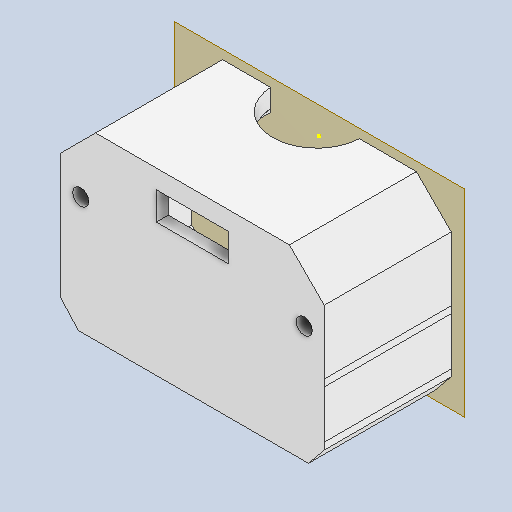
# Autodesk Inventor part: деталька крепления часть первая
Saved by Autodesk Inventor 2024.2 (Build 282272000, 272)
## iProperties
Created: 2026-09-02
Part Number: деталька крепления часть первая
Material: PLA
Document SubType Name: Modeling
Designer: katya_notebook
Density: 1.24 g/cm^3
Appearance: Типовые
Author: katya_notebook
Autodesk Inventor part; units mm, degrees
ref_plane "YZ Plane" through (0, 0, 0) normal (1, 0, 0) x (0, 1, 0)
ref_plane "РабПлоскость1" through (0, 0, 0) normal (0, 0, 1) x (1, 0, 0)
sketch "Эскиз1" plane through (0, 0, 0) normal (0, 0, 1) x (1, 0, 0)
  line L0 (-22.9, -16.3497) -> (-31.9, -16.3497) projected
  arc A0 (-22.9, -16.3497) -> (-20.9, -14.3497) centre (-22.9, -14.3497) ccw projected
  line L1 (-20.9, -6.3497) -> (-20.9, -14.3497) projected
  arc A1 (-18.9, -4.3497) -> (-20.9, -6.3497) centre (-18.9, -6.3497) ccw projected
  line L2 (-18.9, -4.3497) -> (-17.916, -4.3497) projected
  line L3 (-17.916, -4.3497) -> (-12.1991, -1.0491) projected
  line L4 (9.9767, 0.1785) -> (17.8199, -4.3497) projected
  line L5 (17.8199, -4.3497) -> (18.9, -4.3497) projected
  arc A2 (20.9, -6.3497) -> (18.9, -4.3497) centre (18.9, -6.3497) ccw projected
  line L6 (20.9, -14.3497) -> (20.9, -6.3497) projected
  arc A3 (20.9, -14.3497) -> (22.9, -16.3497) centre (22.9, -14.3497) ccw projected
  line L7 (31.9, -16.3497) -> (22.9, -16.3497) projected
  line L8 (31.9, -20.3042) -> (31.9, -16.3497) projected
  line L9 (31.9036, -22.0088) -> (31.9, -20.3042) projected
  line L10 (31.9036, -33.957) -> (31.9036, -22.0088) projected
  line L11 (31.9065, -35.3056) -> (31.9036, -33.957) projected
  line L12 (28.483, -39.5052) -> (31.9065, -35.3056) projected
  line L13 (-28.0526, -39.5052) -> (28.483, -39.5052) projected
  line L14 (-31.8964, -35.2742) -> (-28.0526, -39.5052) projected
  line L15 (-31.8964, -22.0067) -> (-31.8964, -35.2742) projected
  line L16 (-31.9, -20.3021) -> (-31.8964, -22.0067) projected
  line L17 (-31.9, -16.3497) -> (-31.9, -20.3021) projected
  line L18 (23.0519, -4.3497) -> (23.0958, -4.3497) projected
  line L19 (23.0519, -4.3497) -> (23.0519, -4.066) projected
  arc A4 (23.0958, -4.3497) -> (23.0519, -4.066) centre (21.1025, -4.5129) ccw projected
  line L20 (-32.9, -20.3031) -> (-32.9, -4.3497) projected
  line L21 (-32.8964, -22.0078) -> (-32.9, -20.3031) projected
  line L22 (-32.8964, -35.6606) -> (-32.8964, -22.0078) projected
  line L23 (-28.4952, -40.5052) -> (-32.8964, -35.6606) projected
  line L24 (28.9579, -40.5052) -> (-28.4952, -40.5052) projected
  line L25 (32.9072, -35.6606) -> (28.9579, -40.5052) projected
  line L26 (32.9036, -33.956) -> (32.9072, -35.6606) projected
  line L27 (32.9036, -22.0078) -> (32.9036, -33.956) projected
  line L28 (32.9, -20.3031) -> (32.9036, -22.0078) projected
  line L29 (32.9, -4.3497) -> (32.9, -20.3031) projected
  line L30 (32.9, -4.3497) -> (24.2, 4.3497) projected
  line L31 (24.2, 4.3497) -> (9.9767, 4.3497) projected
  line L32 (-24.2, 4.3497) -> (-32.9, -4.3497) projected
  circle A5 centre (27.9, -11.3497) radius 2 projected
  circle A6 centre (-27.9, -11.3497) radius 2 projected
  line L33 (-12.1991, -1.0491) -> (-12.1991, 4.3497) projected
  line L34 (-12.1991, 4.3497) -> (-24.2, 4.3497) projected
  line L35 (9.9767, 4.3497) -> (9.9767, 0.1785) projected
  point P0 (0, 0)
ref_plane "РабПлоскость2" through (-25.0013, -36.285, 28.7) normal (0, 0, 1) x (0.8927, -0.4506, 0)
extrude "Выдавливание1" add sketch "Эскиз1" along normal up to surface (28.7 mm away) contours L0 L17 L16 L15 L14 L13 L12 L11 L10 L9 L8 L7 A3 L6 A2 L5 L4 L35 L31 L30 L29 L28 L27 L26 L25 L24 L23 L22 L21 L20 L32 L34 L33 L3 L2 A1 L1 A0 | L19 A4 L18 | A5 | A6
sketch "Эскиз2" plane through (-28.4952, -40.5052, 28.7) normal (0, 0, 1) x (1, 0, 0)
  point P0 (28.4952, 40.5052)
sketch "Эскиз3" plane through (-28.4952, -40.5052, 28.7) normal (0, 0, 1) x (1, 0, 0)
  line L0 (57.4531, 0) -> (0, 0) projected
  line L1 (61.4024, 4.8446) -> (57.4531, 0) projected
  line L2 (61.3988, 6.5492) -> (61.4024, 4.8446) projected
  line L3 (61.3988, 18.4974) -> (61.3988, 6.5492) projected
  line L4 (61.3952, 20.2021) -> (61.3988, 18.4974) projected
  line L5 (61.3952, 36.1554) -> (61.3952, 20.2021) projected
  line L6 (52.6952, 44.8549) -> (61.3952, 36.1554) projected
  line L7 (38.4718, 44.8549) -> (52.6952, 44.8549) projected
  line L8 (-4.4048, 36.1554) -> (4.2952, 44.8549) projected
  line L9 (-4.4048, 20.2021) -> (-4.4048, 36.1554) projected
  line L10 (-4.4012, 18.4974) -> (-4.4048, 20.2021) projected
  line L11 (-4.4012, 4.8446) -> (-4.4012, 18.4974) projected
  line L12 (0, 0) -> (-4.4012, 4.8446) projected
  line L13 (46.3151, 36.1554) -> (38.4718, 40.6837) projected
  arc A0 (49.3952, 34.1554) -> (47.3952, 36.1554) centre (47.3952, 34.1554) ccw projected
  line L14 (30.1792, 36.1554) -> (38.2471, 40.8135) projected
  line L15 (38.2471, 40.8135) -> (46.3151, 36.1554) projected
  line L16 (18.6471, 40.8135) -> (26.7151, 36.1554) projected
  line L17 (30.1792, 40.1554) -> (30.1792, 36.1554) projected
  line L18 (26.7151, 40.1554) -> (30.1792, 40.1554) projected
  line L19 (26.7151, 36.1554) -> (26.7151, 40.1554) projected
  line L20 (18.6471, 40.8135) -> (26.7151, 36.1554) projected
  line L21 (10.5792, 36.1554) -> (18.6471, 40.8135) projected
  arc A1 (9.5952, 36.1554) -> (7.5952, 34.1554) centre (9.5952, 34.1554) ccw projected
  line L22 (10.6308, 36.1554) -> (9.6488, 36.1554) projected
  line L23 (7.5952, 34.1554) -> (7.5952, 26.1554) projected
  arc A2 (5.5952, 24.1554) -> (7.5952, 26.1554) centre (5.5952, 26.1554) ccw projected
  line L24 (5.5952, 24.1554) -> (-3.4048, 24.1554) projected
  line L25 (-3.4048, 24.1554) -> (-3.4048, 20.2031) projected
  line L26 (38.4718, 44.8549) -> (4.2952, 44.8549)
  line L27 (38.4718, 40.6837) -> (38.4718, 44.8549) projected
  line L28 (16.2961, 44.8549) -> (16.2961, 39.4561) projected
  point P0 (28.4952, 40.5052)
  constraints: 2 end point, 1 horizontal, 1 point on line
extrude "Выдавливание2" add sketch "Эскиз3" along normal blind 3
sketch "Эскиз4" plane through (0, 0, 0) normal (0, 0, -1) x (-1, 0, 0)
  line L0 (1.7801, -4.3497) -> (-1.684, -4.3497) projected
  line L1 (-1.684, -4.3497) -> (1.7801, -4.3497)
  line L2 (1.7801, -4.3497) -> (1.7801, -0.3497)
  line L3 (1.7801, -0.3497) -> (-1.684, -0.3497)
  line L4 (-1.684, -0.3497) -> (-1.684, -4.3497)
  point P0 (0, 0)
  dimension "d4" = 4
  dimension "d5" = 3.4641
  constraints: 8 end point, 2 parallel, 1 horizontal, 1 perpendicular
  measures "d4" distance of L3.end L0.end
  measures "d5" distance of L2.end L3.end
extrude "Выдавливание3" cut sketch "Эскиз4" against normal up to surface (31.7 mm away)
sketch "Эскиз5" plane through (0, 0, 0) normal (0, 0, -1) x (-1, 0, 0)
  point P0 (0, 0)
sketch "Эскиз6" plane through (0, 0, 0) normal (0, 0, -1) x (-1, 0, 0)
  circle A0 centre (-27.9, -11.3497) radius 2
  circle A1 centre (27.9, -11.3497) radius 2
  line L0 (-32.9, -20.3031) -> (-32.9, -4.3497) projected
  line L1 (-22.9, -16.3497) -> (-31.9, -16.3497) projected
  line L2 (32.9, -4.3497) -> (32.9, -20.3031) projected
  line L3 (31.9, -16.3497) -> (22.9, -16.3497) projected
  point P0 (0, 0)
  dimension "d10" = 4
  dimension "d11" = 4
  dimension "d12" = 5
  dimension "d13" = 5
  dimension "d14" = 5
  dimension "d15" = 5
  constraints: 2 centre point
  measures "d10" diameter of A0
  measures "d11" diameter of A1
  measures "d12" distance from line of L0 A0.centre
  measures "d13" distance from line of L1 A0.centre
  measures "d14" distance from line of L2 A1.centre
  measures "d15" distance from line of L3 A1.centre
extrude "Выдавливание5" cut sketch "Эскиз6" against normal up to surface (31.7 mm away)
sketch "Эскиз7" plane through (-24.2, 4.3497, 0) normal (0, 1, 0) x (1, 0, 0)
  line L0 (22.4199, 0) -> (22.4199, -31.7) projected
  circle A0 centre (23.0888, 0.5184) radius 11.1 projected
  point P0 (24.2, 0)
extrude "Выдавливание6" cut sketch "Эскиз7" against normal blind 10
ref_plane "РабПлоскость3" through (0, 0, 0) normal (0, 0, 1) x (1, 0, 0)
sketch "Эскиз8" plane through (0, 0, 0) normal (0, 0, 1) x (1, 0, 0)
  line L0 (1.684, -4.3497) -> (9.8643, 0.3732) projected
  line L1 (9.9767, 4.3497) -> (9.9767, 0.1785) projected
  line L2 (24.2, 4.3497) -> (9.9767, 4.3497) projected
  line L3 (1.684, -0.3497) -> (1.684, -4.3497) projected
  line L4 (-1.7801, -0.3497) -> (1.684, -0.3497) projected
  line L5 (-1.7801, -4.3497) -> (-1.7801, -0.3497) projected
  line L6 (-11.0236, 0.987) -> (-1.7801, -4.3497) projected
  line L7 (-17.916, -4.3497) -> (-12.1991, -1.0491) projected
  line L8 (-12.1991, -1.0491) -> (-12.1991, 4.3497) projected
  line L9 (-12.1991, -1.0491) -> (-12.1991, 4.3497)
  line L10 (-12.1991, -1.0491) -> (-6.8003, -1.0491) construction
  line L11 (9.9767, 0.1785) -> (17.8199, -4.3497) projected
  point P0 (0, 0)
  dimension "d20" = 90
  constraints: 4 end point, 1 horizontal, 1 perpendicular, 1 point on line
  measures "d20" angle of L10 L9
extrude "Выдавливание7" [suppressed]
sketch "Эскиз9" plane through (0, 0, 0) normal (0, 0, -1) x (-1, 0, 0)
  line L0 (32.9, -20.3031) -> (32.9, -4.3497) projected
  line L1 (32.8964, -22.0078) -> (32.9, -20.3031) projected
  line L2 (32.8964, -35.6606) -> (32.8964, -22.0078) projected
  line L3 (28.4952, -40.5052) -> (32.8964, -35.6606) projected
  line L4 (-28.9579, -40.5052) -> (28.4952, -40.5052) projected
  line L5 (-32.9072, -35.6606) -> (-28.9579, -40.5052) projected
  line L6 (-32.9036, -33.956) -> (-32.9072, -35.6606) projected
  line L7 (-32.9036, -22.0078) -> (-32.9036, -33.956) projected
  line L8 (-32.9, -20.3031) -> (-32.9036, -22.0078) projected
  line L9 (-32.9, -4.3497) -> (-32.9, -20.3031) projected
  line L10 (-32.9, -4.3497) -> (-24.2, 4.3497) projected
  line L11 (-24.2, 4.3497) -> (-9.9767, 4.3497) projected
  line L12 (24.2, 4.3497) -> (32.9, -4.3497) projected
  line L13 (-23.0519, -4.3497) -> (-23.0958, -4.3497) projected
  line L14 (-23.0519, -4.3497) -> (-23.0519, -4.066) projected
  arc A0 (-23.0519, -4.066) -> (-23.0958, -4.3497) centre (-21.1025, -4.5129) ccw projected
  line L15 (-9.9767, 0.1785) -> (-17.8199, -4.3497) projected
  line L16 (-17.8199, -4.3497) -> (-18.9, -4.3497) projected
  arc A1 (-18.9, -4.3497) -> (-20.9, -6.3497) centre (-18.9, -6.3497) ccw projected
  line L17 (-20.9, -14.3497) -> (-20.9, -6.3497) projected
  arc A2 (-22.9, -16.3497) -> (-20.9, -14.3497) centre (-22.9, -14.3497) ccw projected
  line L18 (-31.9, -16.3497) -> (-22.9, -16.3497) projected
  line L19 (-31.9, -20.3042) -> (-31.9, -16.3497) projected
  line L20 (-31.9036, -22.0088) -> (-31.9, -20.3042) projected
  line L21 (-31.9036, -33.957) -> (-31.9036, -22.0088) projected
  line L22 (-31.9065, -35.3056) -> (-31.9036, -33.957) projected
  line L23 (-28.483, -39.5052) -> (-31.9065, -35.3056) projected
  line L24 (28.0526, -39.5052) -> (-28.483, -39.5052) projected
  line L25 (31.8964, -35.2742) -> (28.0526, -39.5052) projected
  line L26 (31.8964, -22.0067) -> (31.8964, -35.2742) projected
  line L27 (31.9, -20.3021) -> (31.8964, -22.0067) projected
  line L28 (31.9, -16.3497) -> (31.9, -20.3021) projected
  line L29 (22.9, -16.3497) -> (31.9, -16.3497) projected
  arc A3 (20.9, -14.3497) -> (22.9, -16.3497) centre (22.9, -14.3497) ccw projected
  line L30 (20.9, -6.3497) -> (20.9, -14.3497) projected
  arc A4 (20.9, -6.3497) -> (18.9, -4.3497) centre (18.9, -6.3497) ccw projected
  line L31 (18.9, -4.3497) -> (17.916, -4.3497) projected
  line L32 (17.916, -4.3497) -> (12.1991, -1.0491) projected
  circle A5 centre (-27.9, -11.3497) radius 2 projected
  circle A6 centre (27.9, -11.3497) radius 2 projected
  line L33 (12.1991, -1.0491) -> (12.1991, 4.3497) projected
  line L34 (12.1991, 4.3497) -> (24.2, 4.3497) projected
  line L35 (-9.9767, 4.3497) -> (-9.9767, 0.1785) projected
  point P0 (0, 0)
extrude "Выдавливание8" [suppressed]
sketch "Эскиз10" plane through (-28.4952, -40.5052, 31.7) normal (0, 0, 1) x (1, 0, 0)
  line L0 (34.4471, 40.1632) -> (22.4471, 40.1632) projected
  line L1 (22.4471, 40.1632) -> (22.4471, 34.6632) projected
  line L2 (22.4471, 34.6632) -> (34.4471, 34.6632) projected
  line L3 (34.4471, 34.6632) -> (34.4471, 40.1632) projected
  point P0 (28.4952, 40.5052)
extrude "Выдавливание9" cut sketch "Эскиз10" against normal blind 60
sketch "Эскиз11" plane through (0, 0, 28.7) normal (0, 0, -1) x (-1, 0, 0)
  line L0 (-5.9519, -5.842) -> (-5.9519, -1.8856) projected
  line L1 (-17.8199, -4.3497) -> (-9.7519, 0.3083) projected
  line L2 (-18.9, -4.3497) -> (-17.8199, -4.3497) projected
  line L3 (-20.9, -14.3497) -> (-20.9, -6.3497) projected
  arc A0 (-22.9, -16.3497) -> (-20.9, -14.3497) centre (-22.9, -14.3497) ccw projected
  line L4 (-31.9, -16.3497) -> (-22.9, -16.3497) projected
  line L5 (-31.9, -20.3042) -> (-31.9, -16.3497) projected
  line L6 (-31.9036, -22.0088) -> (-31.9, -20.3042) projected
  line L7 (-31.9036, -33.957) -> (-31.9036, -22.0088) projected
  line L8 (-31.9065, -35.3056) -> (-31.9036, -33.957) projected
  line L9 (-28.483, -39.5052) -> (-31.9065, -35.3056) projected
  line L10 (28.0526, -39.5052) -> (-28.483, -39.5052) projected
  line L11 (31.8964, -35.2742) -> (28.0526, -39.5052) projected
  line L12 (31.8964, -22.0067) -> (31.8964, -35.2742) projected
  line L13 (31.9, -20.3021) -> (31.8964, -22.0067) projected
  line L14 (31.9, -16.3497) -> (31.9, -20.3021) projected
  line L15 (22.9, -16.3497) -> (31.9, -16.3497) projected
  arc A1 (20.9, -14.3497) -> (22.9, -16.3497) centre (22.9, -14.3497) ccw projected
  line L16 (20.9, -6.3497) -> (20.9, -14.3497) projected
  line L17 (17.916, -4.3497) -> (18.9, -4.3497) projected
  line L18 (6.0481, -1.8856) -> (6.0481, -5.842) projected
  line L19 (6.0481, -5.842) -> (-5.9519, -5.842) projected
  line L20 (-5.9519, -1.8856) -> (-9.7519, 0.3083) projected
  arc A2 (-18.9, -4.3497) -> (-20.9, -6.3497) centre (-18.9, -6.3497) ccw projected
  arc A3 (20.9, -6.3497) -> (18.9, -4.3497) centre (18.9, -6.3497) ccw projected
  line L21 (17.916, -4.3497) -> (9.8481, 0.3083) projected
  line L22 (9.8481, 0.3083) -> (6.0481, -1.8856) projected
  point P0 (0, 0)
extrude "Выдавливание10" [suppressed]
sketch "Эскиз12" plane through (-28.4952, -40.5052, 31.7) normal (0, 0, 1) x (1, 0, 0)
  line L0 (37.4471, 33.1632) -> (19.4471, 33.1632)
  line L1 (19.4471, 33.1632) -> (19.4471, 40.1632)
  line L2 (19.4471, 40.1632) -> (37.4471, 40.1632)
  line L3 (37.4471, 40.1632) -> (37.4471, 33.1632)
  line L4 (22.4471, 40.1632) -> (34.4471, 40.1632) projected
  point P0 (28.4952, 40.5052)
  point P1 (28.4471, 40.1632)
  dimension "d29" = 18
  dimension "d30" = 7
  constraints: 8 end point, 2 midpoint, 2 parallel, 1 horizontal, 1 perpendicular
  measures "d29" distance of L0.start L0.end
  measures "d30" distance of L0.end L1.end
extrude "Выдавливание11" cut sketch "Эскиз12" against normal blind 35
sketch "Эскиз14" plane through (9.9767, 4.3497, 0) normal (0, 1, 0) x (1, 0, 0)
  line L0 (0, 0) -> (0, -28.7) projected
  line L1 (0, -28.7) -> (-22.1758, -28.7) projected
  line L2 (-22.1758, 0) -> (-22.1758, -28.7) projected
  circle A0 centre (-11.0879, 0.5184) radius 11.1 projected
  point P0 (-9.9767, 0)
ref_plane "РабПлоскость4" through (-6.6757, -0.342, -39.8964) normal (0, -1, 0) x (1, 0, 0)
extrude "Выдавливание12" add sketch "Эскиз14" against normal up to surface (4.6917 mm away) contours L0 L1 L2 A0
